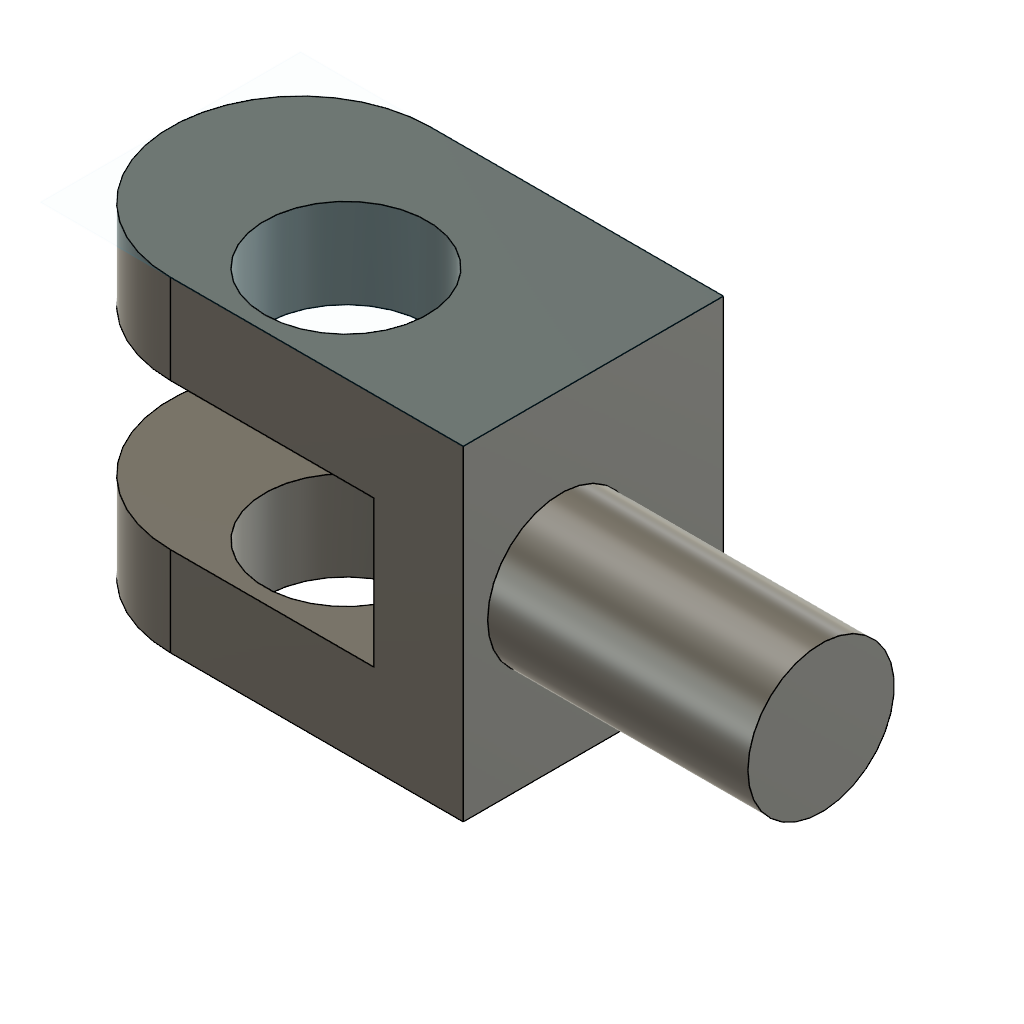
26015028 exercise 3.1(nithish R) (Autodesk Fusion 360 archive; units mm, degrees)
design "nithish R exercise 3.1"
part number: 2026-09-29-15-39-09-270
Autodesk Fusion 360 part; units mm, degrees
sketch "Sketch1" plane through (0, 0, 0) normal (0, 0, 1) x (1, 0, 0)
  line L0 (-26, 0) -> (26, 0)
  line L1 (-26, 40) -> (26, 40)
  line L2 (26, 0) -> (26, 40)
  line L3 (-26, 0) -> (-26, 11)
  line L4 (-26, 40) -> (-26, 29)
  line L5 (-26, 29) -> (15, 29)
  line L6 (15, 29) -> (15, 11)
  line L7 (15, 11) -> (-26, 11)
  point P0 (0, 40)
  dimension "d4" = 11
  dimension "d5" = 11
  dimension "d6" = 41
  dimension "d7" = 18
  dimension "d8" = 41
  constraint midpoint L0 origin
  constraint horizontal L0
  constraint midpoint L1 P0
  constraint horizontal L1
  constraint perpendicular L1 L2
  constraint perpendicular L0 L3
  constraint perpendicular L1 L4
  constraint perpendicular L4 L5
  constraint perpendicular L5 L6
  constraint perpendicular L6 L7
  measures "d4" distance of L0.start L3.end
  measures "d5" distance of L1.start L4.end
  measures "d6" distance of L4.end L5.end
  measures "d7" distance of L5.end L6.end
  measures "d8" distance of L6.end L3.end
extrude "Extrude1" add sketch "Sketch1" along normal blind 32
sketch "Sketch2" plane through (26, 0, 0) normal (1, 0, 0) x (0, 0, -1)
  line L0 (0, 0) -> (0, 40)
  line L1 (0, 40) -> (-32, 40)
  line L2 (-32, 40) -> (-32, 0)
  line L3 (-32, 0) -> (0, 0)
  circle A0 centre (-20, 20) radius 9
  dimension "d11" = 18
  measures "d11" diameter of A0
extrude "Extrude2" add sketch "Sketch2" along normal blind 32 contours A0
sketch "Sketch3" plane through (0, 40, 0) normal (0, 1, 0) x (-1, 0, 0)
  line L0 (-26, 0) -> (26, 0)
  line L1 (26, 0) -> (26, 32)
  line L2 (26, 32) -> (-26, 32)
  line L3 (-26, 32) -> (-26, 0)
hole "Hole1" at (-0.2269, 40, 20.2008) direction (0, -1, 0) diameter 20 depth 50 tip angle 118
fillet "Fillet1" radius 16 4 edges at (-26, 5.5, 32) (-26, 5.5, 0) (-26, 34.5, 0) (-26, 34.5, 32)
